Autodesk Inventor part; units mm, degrees
(part 2 of 2)
extrude "Extrusion5" [suppressed]
sketch "Sketch8" plane through (0, 0, 0) normal (0, 0, -1) x (-1, 0, 0)
  circle A0 centre (-38.1957, 19.3077) radius 1 projected
  circle A1 centre (-57.2458, 95.507) radius 1 projected
  circle A2 centre (-38.1958, 57.407) radius 1 projected
  circle A3 centre (-19.1457, 95.507) radius 1 projected
  line L0 (-3.0951, 114.558) -> (-2.8594, 114.548) projected
  line L1 (-73.2966, 114.558) -> (-3.0951, 114.558) projected
  line L2 (-73.5323, 114.548) -> (-73.2966, 114.558) projected
  line L3 (-73.7651, 114.522) -> (-73.5323, 114.548) projected
  line L4 (-73.9965, 114.475) -> (-73.7651, 114.522) projected
  line L5 (-74.2237, 114.411) -> (-73.9965, 114.475) projected
  line L6 (-74.4442, 114.329) -> (-74.2237, 114.411) projected
  line L7 (-74.658, 114.231) -> (-74.4442, 114.329) projected
  line L8 (-74.8633, 114.115) -> (-74.658, 114.231) projected
  line L9 (-75.0591, 113.986) -> (-74.8633, 114.115) projected
  line L10 (-75.245, 113.84) -> (-75.0591, 113.986) projected
  line L11 (-75.4172, 113.68) -> (-75.245, 113.84) projected
  line L12 (-75.577, 113.506) -> (-75.4172, 113.68) projected
  line L13 (-75.723, 113.322) -> (-75.577, 113.506) projected
  line L14 (-75.8543, 113.126) -> (-75.723, 113.322) projected
  line L15 (-75.97, 112.919) -> (-75.8543, 113.126) projected
  line L16 (-76.0677, 112.705) -> (-75.97, 112.919) projected
  line L17 (-76.1488, 112.485) -> (-76.0677, 112.705) projected
  line L18 (-76.2138, 112.258) -> (-76.1488, 112.485) projected
  line L19 (-76.2593, 112.028) -> (-76.2138, 112.258) projected
  line L20 (-76.2868, 111.794) -> (-76.2593, 112.028) projected
  line L21 (-76.2963, 111.558) -> (-76.2868, 111.794) projected
  line L22 (-76.2963, 3.2563) -> (-76.2963, 111.558) projected
  line L23 (-76.2868, 3.0207) -> (-76.2963, 3.2563) projected
  line L24 (-76.2593, 2.7878) -> (-76.2868, 3.0207) projected
  line L25 (-76.2138, 2.5563) -> (-76.2593, 2.7878) projected
  line L26 (-76.1488, 2.3289) -> (-76.2138, 2.5563) projected
  line L27 (-76.0677, 2.1084) -> (-76.1488, 2.3289) projected
  line L28 (-75.97, 1.8948) -> (-76.0677, 2.1084) projected
  line L29 (-75.8543, 1.6895) -> (-75.97, 1.8948) projected
  line L30 (-75.723, 1.4938) -> (-75.8543, 1.6895) projected
  line L31 (-75.577, 1.3078) -> (-75.723, 1.4938) projected
  line L32 (-75.4172, 1.1355) -> (-75.577, 1.3078) projected
  line L33 (-75.245, 0.9757) -> (-75.4172, 1.1355) projected
  line L34 (-75.0591, 0.8296) -> (-75.245, 0.9757) projected
  line L35 (-74.8633, 0.6987) -> (-75.0591, 0.8296) projected
  line L36 (-74.658, 0.5829) -> (-74.8633, 0.6987) projected
  line L37 (-74.4442, 0.4851) -> (-74.658, 0.5829) projected
  line L38 (-74.2237, 0.4038) -> (-74.4442, 0.4851) projected
  line L39 (-73.9965, 0.339) -> (-74.2237, 0.4038) projected
  line L40 (-73.7651, 0.2935) -> (-73.9965, 0.339) projected
  line L41 (-73.5323, 0.266) -> (-73.7651, 0.2935) projected
  line L42 (-73.2952, 0.2563) -> (-73.5323, 0.266) projected
  line L43 (-3.0951, 0.2563) -> (-73.2952, 0.2563) projected
  line L44 (-2.8594, 0.266) -> (-3.0951, 0.2563) projected
  line L45 (-2.6252, 0.2935) -> (-2.8594, 0.266) projected
  line L46 (-2.395, 0.339) -> (-2.6252, 0.2935) projected
  line L47 (-2.1677, 0.4038) -> (-2.395, 0.339) projected
  line L48 (-1.9472, 0.4851) -> (-2.1677, 0.4038) projected
  line L49 (-1.7336, 0.5829) -> (-1.9472, 0.4851) projected
  line L50 (-1.5269, 0.6987) -> (-1.7336, 0.5829) projected
  line L51 (-1.3312, 0.8296) -> (-1.5269, 0.6987) projected
  line L52 (-1.1465, 0.9757) -> (-1.3312, 0.8296) projected
  line L53 (-0.9729, 1.1355) -> (-1.1465, 0.9757) projected
  line L54 (-0.813, 1.3078) -> (-0.9729, 1.1355) projected
  line L55 (-0.667, 1.4938) -> (-0.813, 1.3078) projected
  line L56 (-0.5374, 1.6895) -> (-0.667, 1.4938) projected
  line L57 (-0.4217, 1.8948) -> (-0.5374, 1.6895) projected
  line L58 (-0.3238, 2.1084) -> (-0.4217, 1.8948) projected
  line L59 (-0.2412, 2.3289) -> (-0.3238, 2.1084) projected
  line L60 (-0.1778, 2.5563) -> (-0.2412, 2.3289) projected
  line L61 (-0.1309, 2.7878) -> (-0.1778, 2.5563) projected
  line L62 (-0.1047, 3.0207) -> (-0.1309, 2.7878) projected
  line L63 (-0.0951, 3.2577) -> (-0.1047, 3.0207) projected
  line L64 (-0.0951, 111.558) -> (-0.0951, 3.2577) projected
  line L65 (-0.1047, 111.794) -> (-0.0951, 111.558) projected
  line L66 (-0.1309, 112.028) -> (-0.1047, 111.794) projected
  line L67 (-0.1778, 112.258) -> (-0.1309, 112.028) projected
  line L68 (-0.2412, 112.485) -> (-0.1778, 112.258) projected
  line L69 (-0.3238, 112.705) -> (-0.2412, 112.485) projected
  line L70 (-0.4217, 112.919) -> (-0.3238, 112.705) projected
  line L71 (-0.5374, 113.126) -> (-0.4217, 112.919) projected
  line L72 (-0.667, 113.322) -> (-0.5374, 113.126) projected
  line L73 (-0.813, 113.506) -> (-0.667, 113.322) projected
  line L74 (-0.9729, 113.68) -> (-0.813, 113.506) projected
  line L75 (-1.1465, 113.84) -> (-0.9729, 113.68) projected
  line L76 (-1.3312, 113.986) -> (-1.1465, 113.84) projected
  line L77 (-1.5269, 114.115) -> (-1.3312, 113.986) projected
  line L78 (-1.7336, 114.231) -> (-1.5269, 114.115) projected
  line L79 (-1.9472, 114.329) -> (-1.7336, 114.231) projected
  line L80 (-2.1677, 114.411) -> (-1.9472, 114.329) projected
  line L81 (-2.395, 114.475) -> (-2.1677, 114.411) projected
  line L82 (-2.6252, 114.522) -> (-2.395, 114.475) projected
  line L83 (-2.8594, 114.548) -> (-2.6252, 114.522) projected
  line L84 (-66.27, 73.5072) -> (-69.07, 73.5072) projected
  line L85 (-66.27, 72.6817) -> (-66.27, 73.5072) projected
  line L86 (-60.0012, 72.6817) -> (-66.27, 72.6817) projected
  line L87 (-60.0012, 70.9581) -> (-60.0012, 72.6817) projected
  line L88 (-58.801, 70.9581) -> (-60.0012, 70.9581) projected
  line L89 (-58.801, 67.6575) -> (-58.801, 70.9581) projected
  line L90 (-60.0012, 67.6575) -> (-58.801, 67.6575) projected
  line L91 (-60.0012, 65.9324) -> (-60.0012, 67.6575) projected
  line L92 (-64.4701, 65.9324) -> (-60.0012, 65.9324) projected
  line L93 (-64.4701, 64.4066) -> (-64.4701, 65.9324) projected
  line L94 (-59.7711, 64.4066) -> (-64.4701, 64.4066) projected
  line L95 (-59.7711, 50.4074) -> (-59.7711, 64.4066) projected
  line L96 (-64.4701, 50.4074) -> (-59.7711, 50.4074) projected
  line L97 (-64.4701, 48.8819) -> (-64.4701, 50.4074) projected
  line L98 (-60.0012, 48.8819) -> (-64.4701, 48.8819) projected
  line L99 (-60.0012, 47.1579) -> (-60.0012, 48.8819) projected
  line L100 (-58.801, 47.1579) -> (-60.0012, 47.1579) projected
  line L101 (-58.801, 43.8573) -> (-58.801, 47.1579) projected
  line L102 (-60.0012, 43.8573) -> (-58.801, 43.8573) projected
  line L103 (-60.0012, 42.1323) -> (-60.0012, 43.8573) projected
  line L104 (-66.27, 42.1323) -> (-60.0012, 42.1323) projected
  line L105 (-66.27, 41.3067) -> (-66.27, 42.1323) projected
  line L106 (-69.07, 41.3067) -> (-66.27, 41.3067) projected
  line L107 (-69.07, 42.1323) -> (-69.07, 41.3067) projected
  line L108 (-72.3, 42.1323) -> (-69.07, 42.1323) projected
  line L109 (-72.3, 48.8819) -> (-72.3, 42.1323) projected
  line L110 (-69.07, 48.8819) -> (-72.3, 48.8819) projected
  line L111 (-69.07, 50.4074) -> (-69.07, 48.8819) projected
  line L112 (-73.7704, 50.4074) -> (-69.07, 50.4074) projected
  line L113 (-73.7704, 64.4066) -> (-73.7704, 50.4074) projected
  line L114 (-69.07, 64.4066) -> (-73.7704, 64.4066) projected
  line L115 (-69.07, 65.9324) -> (-69.07, 64.4066) projected
  line L116 (-72.3, 65.9324) -> (-69.07, 65.9324) projected
  line L117 (-72.3, 72.6817) -> (-72.3, 65.9324) projected
  line L118 (-69.07, 72.6817) -> (-72.3, 72.6817) projected
  line L119 (-69.07, 73.5072) -> (-69.07, 72.6817) projected
  line L120 (-66.27, 35.4072) -> (-69.07, 35.4072) projected
  line L121 (-66.27, 34.5819) -> (-66.27, 35.4072) projected
  line L122 (-60.0012, 34.5819) -> (-66.27, 34.5819) projected
  line L123 (-60.0012, 32.8579) -> (-60.0012, 34.5819) projected
  line L124 (-58.801, 32.8579) -> (-60.0012, 32.8579) projected
  line L125 (-58.801, 29.5576) -> (-58.801, 32.8579) projected
  line L126 (-60.0012, 29.5576) -> (-58.801, 29.5576) projected
  line L127 (-60.0012, 27.8322) -> (-60.0012, 29.5576) projected
  line L128 (-64.4701, 27.8322) -> (-60.0012, 27.8322) projected
  line L129 (-64.4701, 26.3067) -> (-64.4701, 27.8322) projected
  line L130 (-59.7711, 26.3067) -> (-64.4701, 26.3067) projected
  line L131 (-59.7711, 12.3073) -> (-59.7711, 26.3067) projected
  line L132 (-64.4701, 12.3073) -> (-59.7711, 12.3073) projected
  line L133 (-64.4701, 10.7818) -> (-64.4701, 12.3073) projected
  line L134 (-60.0012, 10.7818) -> (-64.4701, 10.7818) projected
  line L135 (-60.0012, 9.0579) -> (-60.0012, 10.7818) projected
  line L136 (-58.801, 9.0579) -> (-60.0012, 9.0579) projected
  line L137 (-58.801, 5.7574) -> (-58.801, 9.0579) projected
  line L138 (-60.0012, 5.7574) -> (-58.801, 5.7574) projected
  line L139 (-60.0012, 4.0321) -> (-60.0012, 5.7574) projected
  line L140 (-66.27, 4.0321) -> (-60.0012, 4.0321) projected
  line L141 (-66.27, 3.2067) -> (-66.27, 4.0321) projected
  line L142 (-69.07, 3.2067) -> (-66.27, 3.2067) projected
  line L143 (-69.07, 4.0321) -> (-69.07, 3.2067) projected
  line L144 (-72.3, 4.0321) -> (-69.07, 4.0321) projected
  line L145 (-72.3, 10.7818) -> (-72.3, 4.0321) projected
  line L146 (-69.07, 10.7818) -> (-72.3, 10.7818) projected
  line L147 (-69.07, 12.3073) -> (-69.07, 10.7818) projected
  line L148 (-73.7704, 12.3073) -> (-69.07, 12.3073) projected
  line L149 (-73.7704, 26.3067) -> (-73.7704, 12.3073) projected
  line L150 (-69.07, 26.3067) -> (-73.7704, 26.3067) projected
  line L151 (-69.07, 27.8322) -> (-69.07, 26.3067) projected
  line L152 (-72.3, 27.8322) -> (-69.07, 27.8322) projected
  line L153 (-72.3, 34.5819) -> (-72.3, 27.8322) projected
  line L154 (-69.07, 34.5819) -> (-72.3, 34.5819) projected
  line L155 (-69.07, 35.4072) -> (-69.07, 34.5819) projected
  line L156 (-3.8709, 4.2539) -> (-3.8709, 7.4841) projected
  line L157 (-10.6206, 4.2539) -> (-3.8709, 4.2539) projected
  line L158 (-10.6206, 7.4827) -> (-10.6206, 4.2539) projected
  line L159 (-12.146, 7.4827) -> (-10.6206, 7.4827) projected
  line L160 (-12.146, 2.7836) -> (-12.146, 7.4827) projected
  line L161 (-26.1455, 2.7836) -> (-12.146, 2.7836) projected
  line L162 (-26.1455, 7.4827) -> (-26.1455, 2.7836) projected
  line L163 (-27.671, 7.4827) -> (-26.1455, 7.4827) projected
  line L164 (-27.671, 4.2539) -> (-27.671, 7.4827) projected
  line L165 (-34.4206, 4.2539) -> (-27.671, 4.2539) projected
  line L166 (-34.4206, 7.4841) -> (-34.4206, 4.2539) projected
  line L167 (-35.2461, 7.4841) -> (-34.4206, 7.4841) projected
  line L168 (-35.2461, 10.2829) -> (-35.2461, 7.4841) projected
  line L169 (-34.4206, 10.2829) -> (-35.2461, 10.2829) projected
  line L170 (-34.4206, 16.553) -> (-34.4206, 10.2829) projected
  line L171 (-32.6953, 16.553) -> (-34.4206, 16.553) projected
  line L172 (-32.6953, 17.7532) -> (-32.6953, 16.553) projected
  line L173 (-29.3949, 17.7532) -> (-32.6953, 17.7532) projected
  line L174 (-29.3949, 16.553) -> (-29.3949, 17.7532) projected
  line L175 (-27.671, 16.553) -> (-29.3949, 16.553) projected
  line L176 (-27.671, 12.0826) -> (-27.671, 16.553) projected
  line L177 (-26.1455, 12.0826) -> (-27.671, 12.0826) projected
  line L178 (-26.1455, 16.7831) -> (-26.1455, 12.0826) projected
  line L179 (-12.146, 16.7831) -> (-26.1455, 16.7831) projected
  line L180 (-12.146, 12.0826) -> (-12.146, 16.7831) projected
  line L181 (-10.6206, 12.0826) -> (-12.146, 12.0826) projected
  line L182 (-10.6206, 16.553) -> (-10.6206, 12.0826) projected
  line L183 (-8.8952, 16.553) -> (-10.6206, 16.553) projected
  line L184 (-8.8952, 17.7532) -> (-8.8952, 16.553) projected
  line L185 (-5.5948, 17.7532) -> (-8.8952, 17.7532) projected
  line L186 (-5.5948, 16.553) -> (-5.5948, 17.7532) projected
  line L187 (-3.8709, 16.553) -> (-5.5948, 16.553) projected
  line L188 (-3.8709, 10.2829) -> (-3.8709, 16.553) projected
  line L189 (-3.0441, 10.2829) -> (-3.8709, 10.2829) projected
  line L190 (-3.0441, 7.4841) -> (-3.0441, 10.2829) projected
  line L191 (-3.8709, 7.4841) -> (-3.0441, 7.4841) projected
  line L192 (-58.7711, 97.0324) -> (-58.7711, 113.032)
  line L193 (-58.7711, 113.032) -> (-74.7704, 113.032)
  line L194 (-74.7704, 113.032) -> (-74.7704, 97.0324)
  line L195 (-74.7704, 97.0324) -> (-58.7711, 97.0324)
  line L196 (-73.7704, 113.032) -> (-73.7704, 97.0324)
  line L197 (-59.7711, 113.032) -> (-59.7711, 97.0324)
  line L198 (-59.7711, 112.032) -> (-73.7704, 112.032) construction
  line L199 (-66.7708, 112.032) -> (-66.7708, 107.7772) construction
  line L200 (-73.7704, 112.032) -> (-73.7704, 98.0324) construction
  line L201 (-73.7704, 105.0322) -> (-70.685, 105.0322) construction
  line L202 (-55.7204, 97.0324) -> (-39.7211, 97.0324)
  line L203 (-40.7211, 113.032) -> (-40.7211, 97.0324)
  line L204 (-39.7211, 113.032) -> (-55.7204, 113.032)
  line L205 (-54.7204, 113.032) -> (-54.7204, 97.0324)
  line L206 (-36.6704, 97.0324) -> (-20.6711, 97.0324)
  line L207 (-21.6711, 113.032) -> (-21.6711, 97.0324)
  line L208 (-20.6711, 113.032) -> (-36.6704, 113.032)
  line L209 (-35.6704, 113.032) -> (-35.6704, 97.0324)
  line L210 (-17.6204, 97.0324) -> (-1.6211, 97.0324)
  line L211 (-2.6211, 113.032) -> (-2.6211, 97.0324)
  line L212 (-1.6211, 113.032) -> (-17.6204, 113.032)
  line L213 (-16.6204, 113.032) -> (-16.6204, 97.0324)
  circle A4 centre (-57.2458, 95.507) radius 1 construction
  line L214 (-57.2458, 95.507) -> (-69.4201, 95.507) construction
  line L215 (-59.7711, 92.9816) -> (-59.7711, 78.982)
  line L216 (-73.7704, 78.982) -> (-73.7704, 92.9816)
  line L217 (-58.7711, 77.982) -> (-74.7704, 77.982)
  line L218 (-74.7704, 93.9816) -> (-58.7711, 93.9816)
  line L219 (-73.7704, 77.982) -> (-73.7704, 93.9816)
  line L220 (-59.7711, 77.982) -> (-59.7711, 93.9816)
  line L221 (-16.6204, 93.982) -> (-16.6204, 77.9824)
  line L222 (-21.6711, 93.982) -> (-21.6711, 77.9824)
  line L223 (-54.7204, 93.982) -> (-54.7204, 77.9824)
  line L224 (-40.7211, 93.982) -> (-40.7211, 77.9824)
  line L225 (-39.7211, 93.982) -> (-55.7204, 93.982)
  line L226 (-55.7204, 77.9824) -> (-39.7211, 77.9824)
  line L227 (-35.6704, 93.982) -> (-35.6704, 77.9824)
  line L228 (-36.6704, 77.9824) -> (-20.6711, 77.9824)
  line L229 (-20.6711, 93.982) -> (-36.6704, 93.982)
  line L230 (-1.6211, 93.982) -> (-17.6204, 93.982)
  line L231 (-2.6211, 93.982) -> (-2.6211, 77.9824)
  line L232 (-17.6204, 77.9824) -> (-1.6211, 77.9824)
  line L233 (-16.6204, 74.932) -> (-16.6204, 58.9324)
  line L234 (-21.6711, 74.932) -> (-21.6711, 58.9324)
  line L235 (-54.7204, 74.932) -> (-54.7204, 58.9324)
  line L236 (-40.7211, 74.932) -> (-40.7211, 58.9324)
  line L237 (-39.7211, 74.932) -> (-55.7204, 74.932)
  line L238 (-55.7204, 58.9324) -> (-39.7211, 58.9324)
  line L239 (-35.6704, 74.932) -> (-35.6704, 58.9324)
  line L240 (-36.6704, 58.9324) -> (-20.6711, 58.9324)
  line L241 (-20.6711, 74.932) -> (-36.6704, 74.932)
  line L242 (-1.6211, 74.932) -> (-17.6204, 74.932)
  line L243 (-2.6211, 74.932) -> (-2.6211, 58.9324)
  line L244 (-17.6204, 58.9324) -> (-1.6211, 58.9324)
  line L245 (-16.6204, 55.882) -> (-16.6204, 39.8824)
  line L246 (-21.6711, 55.882) -> (-21.6711, 39.8824)
  line L247 (-54.7204, 55.882) -> (-54.7204, 39.8824)
  line L248 (-40.7211, 55.882) -> (-40.7211, 39.8824)
  line L249 (-39.7211, 55.882) -> (-55.7204, 55.882)
  line L250 (-55.7204, 39.8824) -> (-39.7211, 39.8824)
  line L251 (-35.6704, 55.882) -> (-35.6704, 39.8824)
  line L252 (-36.6704, 39.8824) -> (-20.6711, 39.8824)
  line L253 (-20.6711, 55.882) -> (-36.6704, 55.882)
  line L254 (-1.6211, 55.882) -> (-17.6204, 55.882)
  line L255 (-2.6211, 55.882) -> (-2.6211, 39.8824)
  line L256 (-17.6204, 39.8824) -> (-1.6211, 39.8824)
  line L257 (-16.6204, 36.832) -> (-16.6204, 20.8324)
  line L258 (-21.6711, 36.832) -> (-21.6711, 20.8324)
  line L259 (-54.7204, 36.832) -> (-54.7204, 20.8324)
  line L260 (-40.7211, 36.832) -> (-40.7211, 20.8324)
  line L261 (-39.7211, 36.832) -> (-55.7204, 36.832)
  line L262 (-55.7204, 20.8324) -> (-39.7211, 20.8324)
  line L263 (-35.6704, 36.832) -> (-35.6704, 20.8324)
  line L264 (-36.6704, 20.8324) -> (-20.6711, 20.8324)
  line L265 (-20.6711, 36.832) -> (-36.6704, 36.832)
  line L266 (-1.6211, 36.832) -> (-17.6204, 36.832)
  line L267 (-2.6211, 36.832) -> (-2.6211, 20.8324)
  line L268 (-17.6204, 20.8324) -> (-1.6211, 20.8324)
  circle A5 centre (-38.1957, 19.3077) radius 1 construction
  line L269 (-38.1957, 19.3077) -> (-47.7207, 19.3077) construction
  line L270 (-54.7204, 1.7834) -> (-54.7204, 17.783)
  line L271 (-40.7211, 1.7834) -> (-40.7211, 17.783)
  line L272 (-39.7211, 1.7834) -> (-55.7204, 1.7834)
  line L273 (-55.7204, 17.783) -> (-39.7211, 17.783)
  point P0 (0, 0)
  dimension "d60" = 19.05
  dimension "d67" = 19.05
  constraints: 160 end point, 72 point on line, 18 symmetric about line, 4 horizontal, 2 midpoint, 2 perpendicular, 2 vertical, 180 other
  measures "d60" distance of L194.end L202.start
  measures "d67" distance of L207.start L222.start
extrude "Extrusion8" cut sketch "Sketch8" against normal blind 1.5 contours L195 L196 L193 L197 | L205 L204 L203 L202 | L209 L208 L207 L206 | L213 L212 L211 L210 | L215 L220 L217 L219 L216 L218 | L230 L231 L232 L221 | L222 L228 L227 L229 | L225 L224 L226 L223 | L242 L243 L244 L233 | L234 L240 L239 L241 | L237 L236 L238 L235 | L254 L255 L256 L245 | L246 L252 L251 L253 | L249 L248 L250 L247 | L266 L267 L268 L257 | L258 L264 L263 L265 | L261 L260 L262 L259 | L270 L273 L271 L272
extrude "Extrusion6" cut sketch "Sketch4" against normal blind 1.5 contours A1 | A3 | A13 | A17
chamfer "Chamfer1" distance 0.25 angle 45 12 edges at (18.1457, 95.507, 1.5) (17.1457, 95.507, 3) (56.2458, 95.507, 1.5) (55.2458, 95.507, 3) (36.1958, 57.407, 3) (36.1957, 19.3077, 3) (37.1958, 57.407, 1.5) (36.1958, 57.407, 1.5) (17.1457, 95.507, 1.5) (55.2458, 95.507, 1.5) (36.1957, 19.3077, 1.5) (37.1957, 19.3077, 1.5)
sketch "Sketch7" plane through (0, 0, 0) normal (0, 0, -1) x (-1, 0, 0)
  circle A0 centre (-57.2458, 95.507) radius 1 projected
  circle A1 centre (-19.1457, 95.507) radius 1 projected
  line L0 (-3.0951, 114.558) -> (-2.8594, 114.548) projected
  line L1 (-73.2966, 114.558) -> (-3.0951, 114.558) projected
  line L2 (-73.5323, 114.548) -> (-73.2966, 114.558) projected
  line L3 (-73.7651, 114.522) -> (-73.5323, 114.548) projected
  line L4 (-73.9965, 114.475) -> (-73.7651, 114.522) projected
  line L5 (-74.2237, 114.411) -> (-73.9965, 114.475) projected
  line L6 (-74.4442, 114.329) -> (-74.2237, 114.411) projected
  line L7 (-74.658, 114.231) -> (-74.4442, 114.329) projected
  line L8 (-74.8633, 114.115) -> (-74.658, 114.231) projected
  line L9 (-75.0591, 113.986) -> (-74.8633, 114.115) projected
  line L10 (-75.245, 113.84) -> (-75.0591, 113.986) projected
  line L11 (-75.4172, 113.68) -> (-75.245, 113.84) projected
  line L12 (-75.577, 113.506) -> (-75.4172, 113.68) projected
  line L13 (-75.723, 113.322) -> (-75.577, 113.506) projected
  line L14 (-75.8543, 113.126) -> (-75.723, 113.322) projected
  line L15 (-75.97, 112.919) -> (-75.8543, 113.126) projected
  line L16 (-76.0677, 112.705) -> (-75.97, 112.919) projected
  line L17 (-76.1488, 112.485) -> (-76.0677, 112.705) projected
  line L18 (-76.2138, 112.258) -> (-76.1488, 112.485) projected
  line L19 (-76.2593, 112.028) -> (-76.2138, 112.258) projected
  line L20 (-76.2868, 111.794) -> (-76.2593, 112.028) projected
  line L21 (-76.2963, 111.558) -> (-76.2868, 111.794) projected
  line L22 (-76.2963, 3.2563) -> (-76.2963, 111.558) projected
  line L23 (-76.2868, 3.0207) -> (-76.2963, 3.2563) projected
  line L24 (-76.2593, 2.7878) -> (-76.2868, 3.0207) projected
  line L25 (-76.2138, 2.5563) -> (-76.2593, 2.7878) projected
  line L26 (-76.1488, 2.3289) -> (-76.2138, 2.5563) projected
  line L27 (-76.0677, 2.1084) -> (-76.1488, 2.3289) projected
  line L28 (-75.97, 1.8948) -> (-76.0677, 2.1084) projected
  line L29 (-75.8543, 1.6895) -> (-75.97, 1.8948) projected
  line L30 (-75.723, 1.4938) -> (-75.8543, 1.6895) projected
  line L31 (-75.577, 1.3078) -> (-75.723, 1.4938) projected
  line L32 (-75.4172, 1.1355) -> (-75.577, 1.3078) projected
  line L33 (-75.245, 0.9757) -> (-75.4172, 1.1355) projected
  line L34 (-75.0591, 0.8296) -> (-75.245, 0.9757) projected
  line L35 (-74.8633, 0.6987) -> (-75.0591, 0.8296) projected
  line L36 (-74.658, 0.5829) -> (-74.8633, 0.6987) projected
  line L37 (-74.4442, 0.4851) -> (-74.658, 0.5829) projected
  line L38 (-74.2237, 0.4038) -> (-74.4442, 0.4851) projected
  line L39 (-73.9965, 0.339) -> (-74.2237, 0.4038) projected
  line L40 (-73.7651, 0.2935) -> (-73.9965, 0.339) projected
  line L41 (-73.5323, 0.266) -> (-73.7651, 0.2935) projected
  line L42 (-73.2952, 0.2563) -> (-73.5323, 0.266) projected
  line L43 (-3.0951, 0.2563) -> (-73.2952, 0.2563) projected
  line L44 (-2.8594, 0.266) -> (-3.0951, 0.2563) projected
  line L45 (-2.6252, 0.2935) -> (-2.8594, 0.266) projected
  line L46 (-2.395, 0.339) -> (-2.6252, 0.2935) projected
  line L47 (-2.1677, 0.4038) -> (-2.395, 0.339) projected
  line L48 (-1.9472, 0.4851) -> (-2.1677, 0.4038) projected
  line L49 (-1.7336, 0.5829) -> (-1.9472, 0.4851) projected
  line L50 (-1.5269, 0.6987) -> (-1.7336, 0.5829) projected
  line L51 (-1.3312, 0.8296) -> (-1.5269, 0.6987) projected
  line L52 (-1.1465, 0.9757) -> (-1.3312, 0.8296) projected
  line L53 (-0.9729, 1.1355) -> (-1.1465, 0.9757) projected
  line L54 (-0.813, 1.3078) -> (-0.9729, 1.1355) projected
  line L55 (-0.667, 1.4938) -> (-0.813, 1.3078) projected
  line L56 (-0.5374, 1.6895) -> (-0.667, 1.4938) projected
  line L57 (-0.4217, 1.8948) -> (-0.5374, 1.6895) projected
  line L58 (-0.3238, 2.1084) -> (-0.4217, 1.8948) projected
  line L59 (-0.2412, 2.3289) -> (-0.3238, 2.1084) projected
  line L60 (-0.1778, 2.5563) -> (-0.2412, 2.3289) projected
  line L61 (-0.1309, 2.7878) -> (-0.1778, 2.5563) projected
  line L62 (-0.1047, 3.0207) -> (-0.1309, 2.7878) projected
  line L63 (-0.0951, 3.2577) -> (-0.1047, 3.0207) projected
  line L64 (-0.0951, 111.558) -> (-0.0951, 3.2577) projected
  line L65 (-0.1047, 111.794) -> (-0.0951, 111.558) projected
  line L66 (-0.1309, 112.028) -> (-0.1047, 111.794) projected
  line L67 (-0.1778, 112.258) -> (-0.1309, 112.028) projected
  line L68 (-0.2412, 112.485) -> (-0.1778, 112.258) projected
  line L69 (-0.3238, 112.705) -> (-0.2412, 112.485) projected
  line L70 (-0.4217, 112.919) -> (-0.3238, 112.705) projected
  line L71 (-0.5374, 113.126) -> (-0.4217, 112.919) projected
  line L72 (-0.667, 113.322) -> (-0.5374, 113.126) projected
  line L73 (-0.813, 113.506) -> (-0.667, 113.322) projected
  line L74 (-0.9729, 113.68) -> (-0.813, 113.506) projected
  line L75 (-1.1465, 113.84) -> (-0.9729, 113.68) projected
  line L76 (-1.3312, 113.986) -> (-1.1465, 113.84) projected
  line L77 (-1.5269, 114.115) -> (-1.3312, 113.986) projected
  line L78 (-1.7336, 114.231) -> (-1.5269, 114.115) projected
  line L79 (-1.9472, 114.329) -> (-1.7336, 114.231) projected
  line L80 (-2.1677, 114.411) -> (-1.9472, 114.329) projected
  line L81 (-2.395, 114.475) -> (-2.1677, 114.411) projected
  line L82 (-2.6252, 114.522) -> (-2.395, 114.475) projected
  line L83 (-2.8594, 114.548) -> (-2.6252, 114.522) projected
  line L84 (-66.27, 73.5072) -> (-69.07, 73.5072) projected
  line L85 (-66.27, 72.6817) -> (-66.27, 73.5072) projected
  line L86 (-60.0012, 72.6817) -> (-66.27, 72.6817) projected
  line L87 (-60.0012, 70.9581) -> (-60.0012, 72.6817) projected
  line L88 (-58.801, 70.9581) -> (-60.0012, 70.9581) projected
  line L89 (-58.801, 67.6575) -> (-58.801, 70.9581) projected
  line L90 (-60.0012, 67.6575) -> (-58.801, 67.6575) projected
  line L91 (-60.0012, 65.9324) -> (-60.0012, 67.6575) projected
  line L92 (-64.4701, 65.9324) -> (-60.0012, 65.9324) projected
  line L93 (-64.4701, 64.4066) -> (-64.4701, 65.9324) projected
  line L94 (-59.7711, 64.4066) -> (-64.4701, 64.4066) projected
  line L95 (-59.7711, 50.4074) -> (-59.7711, 64.4066) projected
  line L96 (-64.4701, 50.4074) -> (-59.7711, 50.4074) projected
  line L97 (-64.4701, 48.8819) -> (-64.4701, 50.4074) projected
  line L98 (-60.0012, 48.8819) -> (-64.4701, 48.8819) projected
  line L99 (-60.0012, 47.1579) -> (-60.0012, 48.8819) projected
  line L100 (-58.801, 47.1579) -> (-60.0012, 47.1579) projected
  line L101 (-58.801, 43.8573) -> (-58.801, 47.1579) projected
  line L102 (-60.0012, 43.8573) -> (-58.801, 43.8573) projected
  line L103 (-60.0012, 42.1323) -> (-60.0012, 43.8573) projected
  line L104 (-66.27, 42.1323) -> (-60.0012, 42.1323) projected
  line L105 (-66.27, 41.3067) -> (-66.27, 42.1323) projected
  line L106 (-69.07, 41.3067) -> (-66.27, 41.3067) projected
  line L107 (-69.07, 42.1323) -> (-69.07, 41.3067) projected
  line L108 (-72.3, 42.1323) -> (-69.07, 42.1323) projected
  line L109 (-72.3, 48.8819) -> (-72.3, 42.1323) projected
  line L110 (-69.07, 48.8819) -> (-72.3, 48.8819) projected
  line L111 (-69.07, 50.4074) -> (-69.07, 48.8819) projected
  line L112 (-73.7704, 50.4074) -> (-69.07, 50.4074) projected
  line L113 (-73.7704, 64.4066) -> (-73.7704, 50.4074) projected
  line L114 (-69.07, 64.4066) -> (-73.7704, 64.4066) projected
  line L115 (-69.07, 65.9324) -> (-69.07, 64.4066) projected
  line L116 (-72.3, 65.9324) -> (-69.07, 65.9324) projected
  line L117 (-72.3, 72.6817) -> (-72.3, 65.9324) projected
  line L118 (-69.07, 72.6817) -> (-72.3, 72.6817) projected
  line L119 (-69.07, 73.5072) -> (-69.07, 72.6817) projected
  line L120 (-66.27, 35.4072) -> (-69.07, 35.4072) projected
  line L121 (-66.27, 34.5819) -> (-66.27, 35.4072) projected
  line L122 (-60.0012, 34.5819) -> (-66.27, 34.5819) projected
  line L123 (-60.0012, 32.8579) -> (-60.0012, 34.5819) projected
  line L124 (-58.801, 32.8579) -> (-60.0012, 32.8579) projected
  line L125 (-58.801, 29.5576) -> (-58.801, 32.8579) projected
  line L126 (-60.0012, 29.5576) -> (-58.801, 29.5576) projected
  line L127 (-60.0012, 27.8322) -> (-60.0012, 29.5576) projected
  line L128 (-64.4701, 27.8322) -> (-60.0012, 27.8322) projected
  line L129 (-64.4701, 26.3067) -> (-64.4701, 27.8322) projected
  line L130 (-59.7711, 26.3067) -> (-64.4701, 26.3067) projected
  line L131 (-59.7711, 12.3073) -> (-59.7711, 26.3067) projected
  line L132 (-64.4701, 12.3073) -> (-59.7711, 12.3073) projected
  line L133 (-64.4701, 10.7818) -> (-64.4701, 12.3073) projected
  line L134 (-60.0012, 10.7818) -> (-64.4701, 10.7818) projected
  line L135 (-60.0012, 9.0579) -> (-60.0012, 10.7818) projected
  line L136 (-58.801, 9.0579) -> (-60.0012, 9.0579) projected
  line L137 (-58.801, 5.7574) -> (-58.801, 9.0579) projected
  line L138 (-60.0012, 5.7574) -> (-58.801, 5.7574) projected
  line L139 (-60.0012, 4.0321) -> (-60.0012, 5.7574) projected
  line L140 (-66.27, 4.0321) -> (-60.0012, 4.0321) projected
  line L141 (-66.27, 3.2067) -> (-66.27, 4.0321) projected
  line L142 (-69.07, 3.2067) -> (-66.27, 3.2067) projected
  line L143 (-69.07, 4.0321) -> (-69.07, 3.2067) projected
  line L144 (-72.3, 4.0321) -> (-69.07, 4.0321) projected
  line L145 (-72.3, 10.7818) -> (-72.3, 4.0321) projected
  line L146 (-69.07, 10.7818) -> (-72.3, 10.7818) projected
  line L147 (-69.07, 12.3073) -> (-69.07, 10.7818) projected
  line L148 (-73.7704, 12.3073) -> (-69.07, 12.3073) projected
  line L149 (-73.7704, 26.3067) -> (-73.7704, 12.3073) projected
  line L150 (-69.07, 26.3067) -> (-73.7704, 26.3067) projected
  line L151 (-69.07, 27.8322) -> (-69.07, 26.3067) projected
  line L152 (-72.3, 27.8322) -> (-69.07, 27.8322) projected
  line L153 (-72.3, 34.5819) -> (-72.3, 27.8322) projected
  line L154 (-69.07, 34.5819) -> (-72.3, 34.5819) projected
  line L155 (-69.07, 35.4072) -> (-69.07, 34.5819) projected
  line L156 (-12.146, 16.7831) -> (-26.1455, 16.7831) projected
  line L157 (-12.146, 12.0826) -> (-12.146, 16.7831) projected
  line L158 (-10.6206, 12.0826) -> (-12.146, 12.0826) projected
  line L159 (-10.6206, 16.553) -> (-10.6206, 12.0826) projected
  line L160 (-3.8709, 10.2829) -> (-3.8709, 16.553) projected
  line L161 (-3.0441, 7.4841) -> (-3.0441, 10.2829) projected
  line L162 (-3.8709, 4.2539) -> (-3.8709, 7.4841) projected
  line L163 (-10.6206, 7.4827) -> (-10.6206, 4.2539) projected
  line L164 (-12.146, 7.4827) -> (-10.6206, 7.4827) projected
  line L165 (-12.146, 2.7836) -> (-12.146, 7.4827) projected
  line L166 (-26.1455, 2.7836) -> (-12.146, 2.7836) projected
  line L167 (-26.1455, 7.4827) -> (-26.1455, 2.7836) projected
  line L168 (-27.671, 7.4827) -> (-26.1455, 7.4827) projected
  line L169 (-27.671, 4.2539) -> (-27.671, 7.4827) projected
  line L170 (-34.4206, 7.4841) -> (-34.4206, 4.2539) projected
  line L171 (-35.2461, 10.2829) -> (-35.2461, 7.4841) projected
  line L172 (-34.4206, 16.553) -> (-34.4206, 10.2829) projected
  line L173 (-27.671, 12.0826) -> (-27.671, 16.553) projected
  line L174 (-26.1455, 12.0826) -> (-27.671, 12.0826) projected
  line L175 (-26.1455, 16.7831) -> (-26.1455, 12.0826) projected
  line L176 (-10.6206, 4.2539) -> (-3.8709, 4.2539) projected
  line L177 (-34.4206, 4.2539) -> (-27.671, 4.2539) projected
  line L178 (-35.2461, 7.4841) -> (-34.4206, 7.4841) projected
  line L179 (-34.4206, 10.2829) -> (-35.2461, 10.2829) projected
  line L180 (-32.6953, 16.553) -> (-34.4206, 16.553) projected
  line L181 (-32.6953, 17.7532) -> (-32.6953, 16.553) projected
  line L182 (-29.3949, 17.7532) -> (-32.6953, 17.7532) projected
  line L183 (-29.3949, 16.553) -> (-29.3949, 17.7532) projected
  line L184 (-27.671, 16.553) -> (-29.3949, 16.553) projected
  line L185 (-8.8952, 16.553) -> (-10.6206, 16.553) projected
  line L186 (-8.8952, 17.7532) -> (-8.8952, 16.553) projected
  line L187 (-5.5948, 17.7532) -> (-8.8952, 17.7532) projected
  line L188 (-5.5948, 16.553) -> (-5.5948, 17.7532) projected
  line L189 (-3.8709, 16.553) -> (-5.5948, 16.553) projected
  line L190 (-3.0441, 10.2829) -> (-3.8709, 10.2829) projected
  line L191 (-3.8709, 7.4841) -> (-3.0441, 7.4841) projected
  line L192 (-65.27, 73.6817) -> (-65.27, 74.5072)
  line L193 (-65.27, 74.5072) -> (-70.07, 74.5072)
  line L194 (-70.07, 74.5072) -> (-70.07, 73.6817)
  line L195 (-70.07, 73.6817) -> (-73.3, 73.6817)
  line L196 (-73.3, 73.6817) -> (-73.3, 65.4066)
  line L197 (-73.3, 65.4066) -> (-74.7704, 65.4066)
  line L198 (-74.7704, 65.4066) -> (-74.7704, 49.4074)
  line L199 (-74.7704, 49.4074) -> (-73.3, 49.4074)
  line L200 (-73.3, 49.4074) -> (-73.3, 41.1323)
  line L201 (-73.3, 41.1323) -> (-70.07, 41.1323)
  line L202 (-70.07, 41.1323) -> (-70.07, 40.3067)
  line L203 (-70.07, 40.3067) -> (-65.27, 40.3067)
  line L204 (-65.27, 40.3067) -> (-65.27, 41.1323)
  line L205 (-65.27, 41.1323) -> (-59.0012, 41.1323)
  line L206 (-59.0012, 41.1323) -> (-59.0012, 42.8573)
  line L207 (-59.0012, 42.8573) -> (-57.801, 42.8573)
  line L208 (-57.801, 42.8573) -> (-57.801, 48.1579)
  line L209 (-57.801, 48.1579) -> (-59.0012, 48.1579)
  line L210 (-59.0012, 48.1579) -> (-59.0012, 49.4074)
  line L211 (-59.0012, 49.4074) -> (-58.7711, 49.4074)
  line L212 (-58.7711, 49.4074) -> (-58.7711, 65.4066)
  line L213 (-58.7711, 65.4066) -> (-59.0012, 65.4066)
  line L214 (-59.0012, 65.4066) -> (-59.0012, 66.6575)
  line L215 (-59.0012, 66.6575) -> (-57.801, 66.6575)
  line L216 (-57.801, 66.6575) -> (-57.801, 71.9581)
  line L217 (-57.801, 71.9581) -> (-59.0012, 71.9581)
  line L218 (-59.0012, 71.9581) -> (-59.0012, 73.6817)
  line L219 (-59.0012, 73.6817) -> (-65.27, 73.6817)
  line L220 (-59.0012, 73.6817) -> (-56.8653, 73.6817)
  line L221 (-59.0012, 41.1323) -> (-56.8653, 41.1323)
  line L222 (-56.8653, 0.2563) -> (-56.8653, 76.4563) projected
  line L223 (-65.27, 35.5819) -> (-65.27, 36.4072)
  line L224 (-65.27, 36.4072) -> (-70.07, 36.4072)
  line L225 (-70.07, 36.4072) -> (-70.07, 35.5819)
  line L226 (-70.07, 35.5819) -> (-73.3, 35.5819)
  line L227 (-73.3, 35.5819) -> (-73.3, 27.3067)
  line L228 (-73.3, 27.3067) -> (-74.7704, 27.3067)
  line L229 (-74.7704, 27.3067) -> (-74.7704, 11.3073)
  line L230 (-74.7704, 11.3073) -> (-73.3, 11.3073)
  line L231 (-73.3, 11.3073) -> (-73.3, 3.0321)
  line L232 (-73.3, 3.0321) -> (-70.07, 3.0321)
  line L233 (-70.07, 3.0321) -> (-70.07, 2.2067)
  line L234 (-70.07, 2.2067) -> (-65.27, 2.2067)
  line L235 (-65.27, 2.2067) -> (-65.27, 3.0321)
  line L236 (-65.27, 3.0321) -> (-59.0012, 3.0321)
  line L237 (-59.0012, 3.0321) -> (-59.0012, 4.7574)
  line L238 (-59.0012, 4.7574) -> (-57.801, 4.7574)
  line L239 (-57.801, 4.7574) -> (-57.801, 10.0579)
  line L240 (-57.801, 10.0579) -> (-59.0012, 10.0579)
  line L241 (-59.0012, 10.0579) -> (-59.0012, 11.3073)
  line L242 (-59.0012, 11.3073) -> (-58.7711, 11.3073)
  line L243 (-58.7711, 11.3073) -> (-58.7711, 27.3067)
  line L244 (-58.7711, 27.3067) -> (-59.0012, 27.3067)
  line L245 (-59.0012, 27.3067) -> (-59.0012, 28.5576)
  line L246 (-59.0012, 28.5576) -> (-57.801, 28.5576)
  line L247 (-57.801, 28.5576) -> (-57.801, 33.8579)
  line L248 (-57.801, 33.8579) -> (-59.0012, 33.8579)
  line L249 (-59.0012, 33.8579) -> (-59.0012, 35.5819)
  line L250 (-59.0012, 35.5819) -> (-65.27, 35.5819)
  line L251 (-59.0012, 35.5819) -> (-56.8653, 35.5819)
  line L252 (-59.0012, 3.0321) -> (-56.8653, 3.0321)
  line L253 (-27.1455, 17.7831) -> (-11.146, 17.7831)
  line L254 (-11.146, 17.7831) -> (-11.146, 17.553)
  line L255 (-11.146, 17.553) -> (-9.8952, 17.553)
  line L256 (-9.8952, 17.553) -> (-9.8952, 18.7532)
  line L257 (-9.8952, 18.7532) -> (-4.5948, 18.7532)
  line L258 (-4.5948, 18.7532) -> (-4.5948, 17.553)
  line L259 (-4.5948, 17.553) -> (-2.8709, 17.553)
  line L260 (-2.8709, 17.553) -> (-2.8709, 11.2829)
  line L261 (-2.8709, 11.2829) -> (-2.0441, 11.2829)
  line L262 (-2.0441, 11.2829) -> (-2.0441, 6.4841)
  line L263 (-2.0441, 6.4841) -> (-2.8709, 6.4841)
  line L264 (-2.8709, 6.4841) -> (-2.8709, 3.2539)
  line L265 (-2.8709, 3.2539) -> (-11.146, 3.2539)
  line L266 (-11.146, 3.2539) -> (-11.146, 1.7836)
  line L267 (-11.146, 1.7836) -> (-27.1455, 1.7836)
  line L268 (-27.1455, 1.7836) -> (-27.1455, 3.2539)
  line L269 (-27.1455, 3.2539) -> (-35.4206, 3.2539)
  line L270 (-35.4206, 3.2539) -> (-35.4206, 6.4841)
  line L271 (-35.4206, 6.4841) -> (-36.2461, 6.4841)
  line L272 (-36.2461, 6.4841) -> (-36.2461, 11.2829)
  line L273 (-36.2461, 11.2829) -> (-35.4206, 11.2829)
  line L274 (-35.4206, 11.2829) -> (-35.4206, 17.553)
  line L275 (-35.4206, 17.553) -> (-33.6953, 17.553)
  line L276 (-33.6953, 17.553) -> (-33.6953, 18.7532)
  line L277 (-33.6953, 18.7532) -> (-28.3949, 18.7532)
  line L278 (-28.3949, 18.7532) -> (-28.3949, 17.553)
  line L279 (-28.3949, 17.553) -> (-27.1455, 17.553)
  line L280 (-27.1455, 17.553) -> (-27.1455, 17.7831)
  line L281 (-38.1, 19.6873) -> (0, 19.6873) projected
  line L282 (-35.4206, 17.553) -> (-35.4206, 19.6873)
  line L283 (-2.8709, 17.553) -> (-2.8709, 19.6873)
  dimension "d77" = 1
  dimension "d78" = 1
  dimension "d79" = 1
  constraints: 180 end point, 6 point on line, 3 perpendicular, 2 horizontal, 1 parallel, 81 other
  measures "d77" distance between parallel lines of L86 L219
  measures "d78" distance between parallel lines of L122 L250
  measures "d79" distance between parallel lines of L156 L253
extrude "Extrusion9" cut sketch "Sketch7" against normal blind 1.5 contours L221 L206 L207 L208 L209 L210 L211 L212 L213 L214 L215 L216 L217 L218 L220 L222 | L252 L237 L238 L239 L240 L241 L242 L243 L244 L245 L246 L247 L248 L249 L251 L222 | L283 L259 L258 L257 L256 L255 L254 L253 L280 L279 L278 L277 L276 L275 L282 L281 | L260 L261 L262 L263 L264 L265 L266 L267 L268 L269 L270 L271 L272 L273 L274 L275 L276 L277 L278 L279 L280 L253 L254 L255 L256 L257 L258 L259 | L236 L235 L234 L233 L232 L231 L230 L229 L228 L227 L226 L225 L224 L223 L250 L249 L248 L247 L246 L245 L244 L243 L242 L241 L240 L239 L238 L237 | L205 L204 L203 L202 L201 L200 L199 L198 L197 L196 L195 L194 L193 L192 L219 L218 L217 L216 L215 L214 L213 L212 L211 L210 L209 L208 L207 L206
equation "\"d3\" = 2 * d2"
equation "\"d7\" = 2 * d3"
equation "\"d9\" = d15"
equation "\"d13\" = d15"
equation "\"d17\" = d15"
equation "\"d19\" = d15"
equation "\"d23\" = d15"
equation "\"d2\" = 19.05"
body "Solid1"
